Autodesk Fusion 360 part; units mm, degrees
(part 2 of 2)
component "PURCHASED_M4x9" placed x (1, 0, 0) y (0, -1, 0) z (0, 0, -1) at (-65, 0, 2)
component "PURCHASED_M4x9" placed x (1, 0, 0) y (0, -1, 0) z (0, 0, -1) at (55, 0, 2)
component "PURCHASED_M4x9" placed x (1, 0, 0) y (0, -1, 0) z (0, 0, -1) at (65, 0, 2)
component "PURCHASED_M4x9" placed x (1, 0, 0) y (0, -1, 0) z (0, 0, -1) at (-55, 200, 2)
component "PURCHASED_M4x9" placed x (1, 0, 0) y (0, -1, 0) z (0, 0, -1) at (-65, 200, 2)
component "PURCHASED_M4x9" placed x (1, 0, 0) y (0, -1, 0) z (0, 0, -1) at (55, 200, 2)
component "PURCHASED_M4x9" placed x (1, 0, 0) y (0, -1, 0) z (0, 0, -1) at (65, 200, 2)
component "PencilHolder" placed x (1, 0, 0) y (0, 1, 0) z (0, 0, 1) at (0, 100, 0)
component "SCENE_Desk" placed x (1, 0, 0) y (0, 1, 0) z (0, 0, 1) at (0, 0, 0)
component "SCENE_Paper" placed x (1, 0, 0) y (0, 1, 0) z (0, 0, 1) at (0, 0, 0)
component "SCENE_Pencil" placed x (1, 0, 0) y (0, 1, 0) z (0, 0, 1) at (0, 100, 0)
equation "D = 50 mm" comment "Motor axis spacing; motors at X = +/-D/2, Y = 0"
equation "L1 = 85 mm" comment "Proximal arm length, centre to centre"
equation "L2 = 125 mm" comment "Distal arm length, centre to centre"
equation "Y0 = 50 mm" comment "Workspace near edge (Y)"
equation "WsW = 200 mm" comment "Workspace width (X from -WsW/2 to +WsW/2)"
equation "WsH = 100 mm" comment "Workspace height (Y from Y0 to Y0+WsH)"
equation "Ym = Y0 + WsH / 2" comment "Mirror line Y of the dual five-bar"
equation "PivotY = 2 * Ym" comment "Y of the passive (unmotorized) pivots"
equation "BrgOD = 24.5 mm" comment "Bearing outer diameter (jo)"
equation "BrgID = 5 mm" comment "Bearing bore (ASSUMED 5, jo wrote 48)"
equation "BrgW = 11 mm" comment "Bearing width"
equation "ClrHole = 5.4 mm" comment "M5 clearance hole (the 4 M5x30 bearing axles)"
equation "NutAF = 8 mm" comment "M5 nut across flats (bearing axles)"
equation "NutH = 4 mm" comment "M5 nut height"
equation "M3Clr = 3.4 mm" comment "M3 clearance hole"
equation "M4Clr = 4.4 mm" comment "M4 clearance hole"
equation "M4Pilot = 3.3 mm" comment "M4 self-tapping pilot hole in plastic"
equation "M4L = 9 mm" comment "M4 screw length (jo has only M4x9)"
equation "M4HeadD = 7 mm" comment "M4 socket head diameter"
equation "M4HeadH = 4 mm" comment "M4 socket head height"
equation "M5L = 30 mm" comment "M5 axle screw length (4x M5x30)"
equation "M5HeadD = 8.5 mm" comment "M5 socket head diameter"
equation "M5HeadH = 5 mm" comment "M5 socket head height"
equation "PinD = 8 mm" comment "Printed pin diameter"
equation "PinHole = PinD + 0.3 mm" comment "Eye hole for printed pins"
equation "PinPlay = 0.3 mm" comment "Axial play under pin caps"
equation "CapD = 14 mm" comment "Printed pin cap (washer) diameter"
equation "CapT = 2 mm" comment "Printed pin cap thickness"
equation "PlateFlange = 2 mm" comment "Plate material under the M4 counterbores"
equation "NemaW = 42.3 mm" comment "NEMA17 body width"
equation "NemaL = 40 mm" comment "NEMA17 body length (Tevo Tarantula)"
equation "NemaHole = 31 mm" comment "NEMA17 M3 hole spacing"
equation "NemaBoss = 22.5 mm" comment "NEMA17 centring boss diameter"
equation "Shaft = 5 mm" comment "NEMA17 D-shaft diameter"
equation "ShaftL = 24 mm" comment "NEMA17 shaft length from face"
equation "ArmW = 12 mm" comment "Arm bar width"
equation "ArmT = 6 mm" comment "Arm bar thickness"
equation "Clearance = 0.2 mm" comment "Print clearance"
equation "HubD = 20 mm" comment "Motor shaft hub diameter"
equation "LayerGap = 1 mm" comment "Z gap (washer) between stacked links"
equation "SolW = 13 mm" comment "Solenoid JF-0530B body width (X)"
equation "SolH = 15 mm" comment "Solenoid JF-0530B body height (Y)"
equation "SolL = 30 mm" comment "Solenoid JF-0530B body length (along plunger)"
equation "SolStroke = 10 mm" comment "Solenoid stroke"
equation "SolPlD = 6 mm" comment "Solenoid plunger diameter"
equation "SolTipOut = 5 mm" comment "Plunger protrusion at rest (ASSUMED)"
equation "FrameT = 6 mm" comment "Mount plate thickness"
equation "RailW = 15 mm" comment "Rail width"
equation "RailH = 10 mm" comment "Rail height"
equation "Wall = 3 mm" comment "Wall around bearing seats"
equation "HWall = 2.5 mm" comment "Solenoid holder wall"
equation "FilletR = 3 mm" comment "Arm bar-to-eye fillet"
equation "FootClr = 5 mm" comment "Table clearance below motors"
equation "PhoneT = 10 mm" comment "Phone thickness (with case)"
equation "TipGap = 3 mm" comment "Plunger tip to screen gap at rest"
equation "RailIn = 50 mm" comment "Inner X end of rail cross-arms"
equation "PlateW = 140 mm" comment "Mount plate width (X)"
equation "PlateDp = NemaW + 10 mm" comment "Mount plate depth (Y)"
equation "EyeD = ArmW + 4 mm" comment "Diameter of M5 eyes"
equation "BossD = BrgOD + 2 * Wall" comment "Diameter of bearing bosses"
equation "HubZ0 = FrameT + LayerGap" comment "Bottom Z of motor hub"
equation "HubH = ShaftL + LayerGap - HubZ0" comment "Motor hub height (covers the shaft)"
equation "ZProx = HubZ0 + HubH - ArmT" comment "Bottom Z of proximal arm bars"
equation "Pitch = ArmT + LayerGap" comment "Z pitch of link levels"
equation "ZD1 = ZProx + Pitch" comment "Bottom Z of distal level 1"
equation "ZD2 = ZD1 + Pitch" comment "Bottom Z of distal level 2"
equation "ZPP = ZD1 + 4 * Pitch" comment "Bottom Z of passive proximal arms"
equation "ZJm = ZD2 - LayerGap / 2" comment "Joint plane Z, motor side"
equation "ZJp = ZJm + 2 * Pitch" comment "Joint plane Z, passive side"
equation "ElbowBossH = BrgW + 2 mm" comment "Proximal elbow bearing boss height"
equation "TowerTop = ZPP - LayerGap" comment "Top Z of passive pivot towers"
equation "TableZ = -( NemaL + FootClr )" comment "Table / phone back Z"
equation "SolBot = TableZ + PhoneT + TipGap + SolTipOut" comment "Solenoid body bottom Z"
equation "RailX = WsW / 2 + 30 mm" comment "Rail centre X"
equation "BoltX1 = RailIn + 5 mm" comment "Rail-to-mount bolt 1 X"
equation "BoltX2 = RailIn + 15 mm" comment "Rail-to-mount bolt 2 X"
equation "d77 = PlateW / 2"
equation "d78 = PlateDp / 2"
equation "d79 = PlateW / 2"
equation "d80 = PlateDp / 2"
equation "d81 = FrameT"
equation "d83 = D / 2"
equation "d84 = NemaBoss + 1 mm"
equation "d85 = ( D / 2 + NemaHole / 2 )"
equation "d86 = NemaHole / 2"
equation "d87 = M3Clr"
equation "d88 = ( D / 2 + NemaHole / 2 )"
equation "d89 = NemaHole / 2"
equation "d90 = M3Clr"
equation "d91 = ( D / 2 - NemaHole / 2 )"
equation "d92 = NemaHole / 2"
equation "d93 = M3Clr"
equation "d94 = ( D / 2 - NemaHole / 2 )"
equation "d95 = NemaHole / 2"
equation "d96 = M3Clr"
equation "d97 = D / 2"
equation "d98 = NemaBoss + 1 mm"
equation "d99 = ( D / 2 + NemaHole / 2 )"
equation "d100 = NemaHole / 2"
equation "d101 = M3Clr"
equation "d102 = ( D / 2 + NemaHole / 2 )"
equation "d103 = NemaHole / 2"
equation "d104 = M3Clr"
equation "d105 = ( D / 2 - NemaHole / 2 )"
equation "d106 = NemaHole / 2"
equation "d107 = M3Clr"
equation "d108 = ( D / 2 - NemaHole / 2 )"
equation "d109 = NemaHole / 2"
equation "d110 = M3Clr"
equation "d111 = FrameT"
equation "d113 = BoltX1"
equation "d114 = M4Clr"
equation "d115 = BoltX2"
equation "d116 = M4Clr"
equation "d117 = BoltX1"
equation "d118 = M4Clr"
equation "d119 = BoltX2"
equation "d120 = M4Clr"
equation "d121 = FrameT"
equation "d123 = BoltX1"
equation "d124 = M4HeadD + 1 mm"
equation "d125 = BoltX2"
equation "d126 = M4HeadD + 1 mm"
equation "d127 = BoltX1"
equation "d128 = M4HeadD + 1 mm"
equation "d129 = BoltX2"
equation "d130 = M4HeadD + 1 mm"
equation "d131 = PlateFlange"
equation "d132 = FrameT - PlateFlange"
equation "d134 = ( PlateW / 2 - 18 mm )"
equation "d136 = ( PlateW / 2 - 3 mm )"
equation "d137 = ( PlateDp / 2 - 4 mm )"
equation "d139 = ( PlateW / 2 - 3 mm )"
equation "d140 = ( PlateDp / 2 - 4 mm )"
equation "d141 = ( PlateW / 2 - 18 mm )"
equation "d142 = ( PlateW / 2 - 3 mm )"
equation "d143 = ( PlateDp / 2 - 4 mm )"
equation "d144 = ( PlateW / 2 - 18 mm )"
equation "d146 = ( PlateW / 2 - 3 mm )"
equation "d147 = ( PlateDp / 2 - 4 mm )"
equation "d148 = FrameT"
equation "d150 = ZJm"
equation "d152 = D / 2"
equation "d153 = D / 2"
equation "d154 = PlateW / 2"
equation "d155 = PivotY - PlateDp / 2"
equation "d156 = PlateW / 2"
equation "d157 = PivotY + PlateDp / 2"
equation "d158 = FrameT"
equation "d160 = D / 2"
equation "d161 = PivotY"
equation "d162 = BossD"
equation "d163 = D / 2"
equation "d164 = BossD"
equation "d165 = FrameT"
equation "d166 = TowerTop - FrameT"
equation "d168 = D / 2"
equation "d169 = PivotY"
equation "d170 = BrgOD"
equation "d171 = D / 2"
equation "d172 = BrgOD"
equation "d173 = TowerTop - BrgW"
equation "d174 = BrgW"
equation "d176 = D / 2"
equation "d177 = PivotY"
equation "d178 = M5HeadD + 1.5 mm"
equation "d179 = D / 2"
equation "d180 = M5HeadD + 1.5 mm"
equation "d181 = TowerTop"
equation "d183 = BoltX1"
equation "d184 = PivotY"
equation "d185 = M4Clr"
equation "d186 = BoltX2"
equation "d187 = M4Clr"
equation "d188 = BoltX1"
equation "d189 = M4Clr"
equation "d190 = BoltX2"
equation "d191 = M4Clr"
equation "d192 = FrameT"
equation "d194 = BoltX1"
equation "d195 = PivotY"
equation "d196 = M4HeadD + 1 mm"
equation "d197 = BoltX2"
equation "d198 = M4HeadD + 1 mm"
equation "d199 = BoltX1"
equation "d200 = M4HeadD + 1 mm"
equation "d201 = BoltX2"
equation "d202 = M4HeadD + 1 mm"
equation "d203 = PlateFlange"
equation "d204 = FrameT - PlateFlange"
equation "d206 = ( PlateW / 2 - 18 mm )"
equation "d207 = PivotY - 9 mm"
equation "d208 = ( PlateW / 2 - 3 mm )"
equation "d209 = PivotY - ( PlateDp / 2 - 4 mm )"
equation "d210 = PivotY + 9 mm"
equation "d211 = ( PlateW / 2 - 3 mm )"
equation "d212 = PivotY + ( PlateDp / 2 - 4 mm )"
equation "d213 = ( PlateW / 2 - 18 mm )"
equation "d214 = ( PlateW / 2 - 3 mm )"
equation "d215 = PivotY - ( PlateDp / 2 - 4 mm )"
equation "d216 = ( PlateW / 2 - 18 mm )"
equation "d217 = PivotY + 9 mm"
equation "d218 = ( PlateW / 2 - 3 mm )"
equation "d219 = PivotY + ( PlateDp / 2 - 4 mm )"
equation "d220 = FrameT"
equation "d222 = ZJp"
equation "d224 = D / 2"
equation "d225 = PivotY"
equation "d226 = D / 2"
equation "d227 = RailX - RailW / 2"
equation "d228 = RailW / 2"
equation "d229 = RailX + RailW / 2"
equation "d230 = PivotY + RailW / 2"
equation "d231 = RailIn"
equation "d232 = RailX"
equation "d233 = RailW / 2"
equation "d234 = RailIn"
equation "d235 = PivotY - RailW / 2"
equation "d236 = RailX"
equation "d237 = PivotY + RailW / 2"
equation "d238 = -RailH"
equation "d239 = RailH"
equation "d241 = RailX - RailW / 2"
equation "d242 = RailW / 2"
equation "d243 = RailX + RailW / 2"
equation "d244 = RailW / 2"
equation "d245 = PivotY - RailW / 2"
equation "d246 = RailX + RailW / 2"
equation "d247 = PivotY + RailW / 2"
equation "d248 = TableZ"
equation "d249 = -RailH - TableZ"
equation "d251 = BoltX1"
equation "d252 = M4Pilot"
equation "d253 = BoltX2"
equation "d254 = M4Pilot"
equation "d255 = PivotY"
equation "d256 = M4Pilot"
equation "d257 = BoltX2"
equation "d258 = PivotY"
equation "d259 = M4Pilot"
equation "d260 = -RailH"
equation "d261 = RailH"
equation "d263 = ArmW / 2"
equation "d264 = L1"
equation "d265 = ArmW / 2"
equation "d266 = ZProx"
equation "d267 = ArmT"
equation "d269 = HubD"
equation "d270 = HubZ0"
equation "d271 = HubH"
equation "d273 = L1"
equation "d274 = BossD"
equation "d275 = ZProx + ArmT - ElbowBossH"
equation "d276 = ElbowBossH"
equation "d279 = FilletR"
equation "d280 = Shaft + Clearance"
equation "d281 = HubZ0"
equation "d282 = HubH"
equation "d284 = -( HubD / 2 + 1 mm )"
equation "d286 = L1"
equation "d287 = BrgOD"
equation "d288 = ZProx + ArmT - BrgW"
equation "d289 = BrgW"
equation "d291 = L1"
equation "d292 = M5HeadD + 1.5 mm"
equation "d293 = ZProx + ArmT - ElbowBossH - 1 mm"
equation "d294 = ElbowBossH + 2 mm"
equation "d296 = ZJm"
equation "d298 = L1"
equation "d299 = ArmW / 2"
equation "d300 = L2"
equation "d301 = ArmW / 2"
equation "d302 = ZD2 + LayerGap / 2"
equation "d303 = ArmT"
equation "d305 = L2"
equation "d306 = EyeD"
equation "d307 = ZD2 - LayerGap / 2"
equation "d308 = Pitch"
equation "d310 = EyeD"
equation "d311 = ZD1 - LayerGap / 2"
equation "d312 = 2 * Pitch"
equation "d315 = FilletR"
equation "d316 = PinHole"
equation "d317 = L2"
equation "d318 = PinHole"
equation "d319 = ZD1 - 1 mm"
equation "d320 = 2 * Pitch + 2 mm"
equation "d322 = ArmW / 2"
equation "d323 = L1"
equation "d324 = ArmW / 2"
equation "d325 = ZPP"
equation "d326 = ArmT"
equation "d328 = EyeD"
equation "d329 = L1"
equation "d330 = EyeD"
equation "d331 = ZPP - LayerGap / 2"
equation "d332 = ArmT + LayerGap / 2"
equation "d335 = FilletR"
equation "d336 = BrgID + 3 mm"
equation "d337 = TowerTop"
equation "d338 = ZPP - LayerGap / 2 - TowerTop"
equation "d340 = L1"
equation "d341 = PinD"
equation "d342 = ZD1 + 2 * Pitch - LayerGap / 2 - PinPlay"
equation "d343 = ZPP - ZD1 - 2 * Pitch + PinPlay"
equation "d345 = L1"
equation "d346 = M4Pilot"
equation "d347 = ZD1 + 2 * Pitch - LayerGap / 2 - PinPlay"
equation "d348 = M4L + 1 mm"
equation "d350 = ClrHole"
equation "d351 = TowerTop - 1 mm"
equation "d352 = ZPP + ArmT - TowerTop + 2 mm"
equation "d354 = ZJp"
equation "d356 = L1"
equation "d357 = ( SolW / 2 + Clearance + HWall )"
equation "d358 = ( SolH / 2 + Clearance + HWall )"
equation "d359 = SolW / 2 + Clearance + HWall"
equation "d360 = SolH / 2 + Clearance + HWall"
equation "d361 = SolBot"
equation "d362 = ZProx - SolBot"
equation "d364 = EyeD"
equation "d365 = ZProx"
equation "d366 = ArmT + LayerGap / 2"
equation "d368 = PinD"
equation "d369 = ZProx + ArmT + LayerGap / 2"
equation "d370 = 4 * Pitch + PinPlay"
equation "d372 = M4Pilot"
equation "d373 = ZProx + ArmT + LayerGap / 2 + 4 * Pitch + PinPlay - M4L - 1 mm"
equation "d374 = M4L + 1 mm"
equation "d376 = -( SolW / 2 + Clearance + M4L - 0.5 mm )"
equation "d378 = ( SolW / 2 + Clearance )"
equation "d379 = ( SolH / 2 + Clearance )"
equation "d380 = SolW / 2 + Clearance"
equation "d381 = SolH / 2 + Clearance"
equation "d382 = SolBot"
equation "d383 = SolL"
equation "d385 = SolPlD + 2 mm"
equation "d386 = SolBot + SolL"
equation "d387 = SolStroke"
equation "d389 = -( SolW / 2 + Clearance + M4L )"
equation "d391 = ZJm"
equation "d393 = ZJp"
equation "d395 = PinHole + 1.5 mm"
equation "d396 = ZProx + ArmT"
equation "d397 = LayerGap / 2"
equation "d399 = PinD"
equation "d400 = ZProx + ArmT + LayerGap / 2"
equation "d401 = 2 * Pitch"
equation "d403 = ClrHole"
equation "d404 = ZProx + ArmT - 1 mm"
equation "d405 = 2 * Pitch + 2 mm"
equation "d407 = CapD"
equation "d408 = CapT"
equation "d410 = M4Clr"
equation "d411 = CapT"
equation "d413 = NemaW / 2"
equation "d414 = NemaW / 2"
equation "d415 = NemaW / 2"
equation "d416 = NemaW / 2"
equation "d417 = -NemaL"
equation "d418 = NemaL"
equation "d420 = NemaBoss"
equation "d423 = Shaft"
equation "d424 = ShaftL"
equation "d426 = BrgOD"
equation "d427 = BrgID"
equation "d428 = BrgW"
equation "d430 = SolW / 2"
equation "d431 = SolH / 2"
equation "d432 = SolW / 2"
equation "d433 = SolH / 2"
equation "d434 = SolL"
equation "d436 = SolPlD"
equation "d437 = -SolTipOut"
equation "d438 = SolL + SolTipOut + 3 mm"
equation "d441 = M5L"
equation "d443 = M5HeadD"
equation "d444 = -( M5HeadH )"
equation "d445 = M5HeadH"
equation "d447 = ClrHole"
equation "d448 = NutH"
equation "d451 = M4L"
equation "d453 = M4HeadD"
equation "d454 = -( M4HeadH )"
equation "d455 = M4HeadH"
equation "PencilD = 7 mm" comment "Pencil diameter"
equation "PencilGrip = -0.15 mm" comment "Interference: clip bore = PencilD - PencilGrip"
equation "ClipWall = 2.2 mm" comment "Pencil C-clip wall thickness"
equation "ClipMouth = 0.83 * PencilD" comment "Opening of the C-clip (about 116 deg), the pencil snaps through it"
equation "ClipL = 40 mm" comment "Pencil clip length below the collar"
equation "d478 = PencilD - PencilGrip + 2 * ClipWall"
equation "d479 = ZProx - ClipL"
equation "d480 = ClipL"
equation "d482 = EyeD"
equation "d483 = ZProx"
equation "d484 = ArmT + LayerGap / 2"
equation "d486 = PinD - 0.2 mm"
equation "d487 = ZProx + ArmT + LayerGap / 2"
equation "d488 = 4 * Pitch + PinPlay"
equation "d490 = M4Pilot"
equation "d491 = ZProx + ArmT + LayerGap / 2 + 4 * Pitch + PinPlay - M4L - 1 mm"
equation "d492 = M4L + 1 mm"
equation "d494 = ZProx + ArmT + LayerGap / 2 + 4 * Pitch + PinPlay - M4L - 1 mm"
equation "d495 = M4L + 1 mm"
equation "d497 = PencilD - PencilGrip"
equation "d498 = ZProx - ClipL - 1 mm"
equation "d499 = ClipL + 1 mm"
equation "d501 = ZProx - ClipL - 1 mm"
equation "d502 = ClipL + 1 mm"
equation "d504 = ZProx - ClipL - 1 mm"
equation "d505 = ClipL + 1 mm"
equation "d507 = ClipMouth / 2"
equation "d508 = PencilD + 2 * ClipWall"
equation "d509 = ClipMouth / 2"
equation "d510 = ZProx - ClipL - 1 mm"
equation "d511 = ClipL + 1 mm"
equation "d513 = ZProx - ClipL - 1 mm"
equation "d514 = ClipL + 1 mm"
equation "d516 = ZProx - ClipL - 1 mm"
equation "d517 = ClipL + 1 mm"
equation "d522 = Ym - 190 mm"
equation "d524 = Ym + 190 mm"
equation "d525 = TableZ - 18 mm"
equation "d529 = Ym - 74 mm"
equation "d531 = Ym + 74 mm"
equation "d532 = TableZ"
equation "d535 = PencilD"
equation "d536 = TableZ + 0.1 mm + 7 mm"
equation "d537 = ZProx - TableZ - 0.1 mm - 7 mm"
equation "d540 = TableZ + 0.15 mm"
equation "CableSlotW = 5.8 mm" comment "Solenoid cable slot width (open from the base of the holder)"
equation "d555 = CableSlotW / 2"
equation "d556 = SolW / 2 + Clearance + HWall + 1 mm"
equation "d557 = CableSlotW / 2"
equation "d558 = SolBot - 1 mm"
equation "d559 = ZProx - SolBot + 1 mm"
named bodies: "MotorMount", "PivotMount", "Rail", "ProximalArm", "DistalArm", "PassiveProximalArm", "EffectorHub_SolenoidHolder", "M5Sleeve", "PinCap", "PURCHASED_NEMA17", "PURCHASED_Bearing", "PURCHASED_Solenoid_JF0530B", "PURCHASED_M5x30", "PURCHASED_M5_Nut", "PURCHASED_M4x9", "PencilHolder", "SCENE_Pencil"
